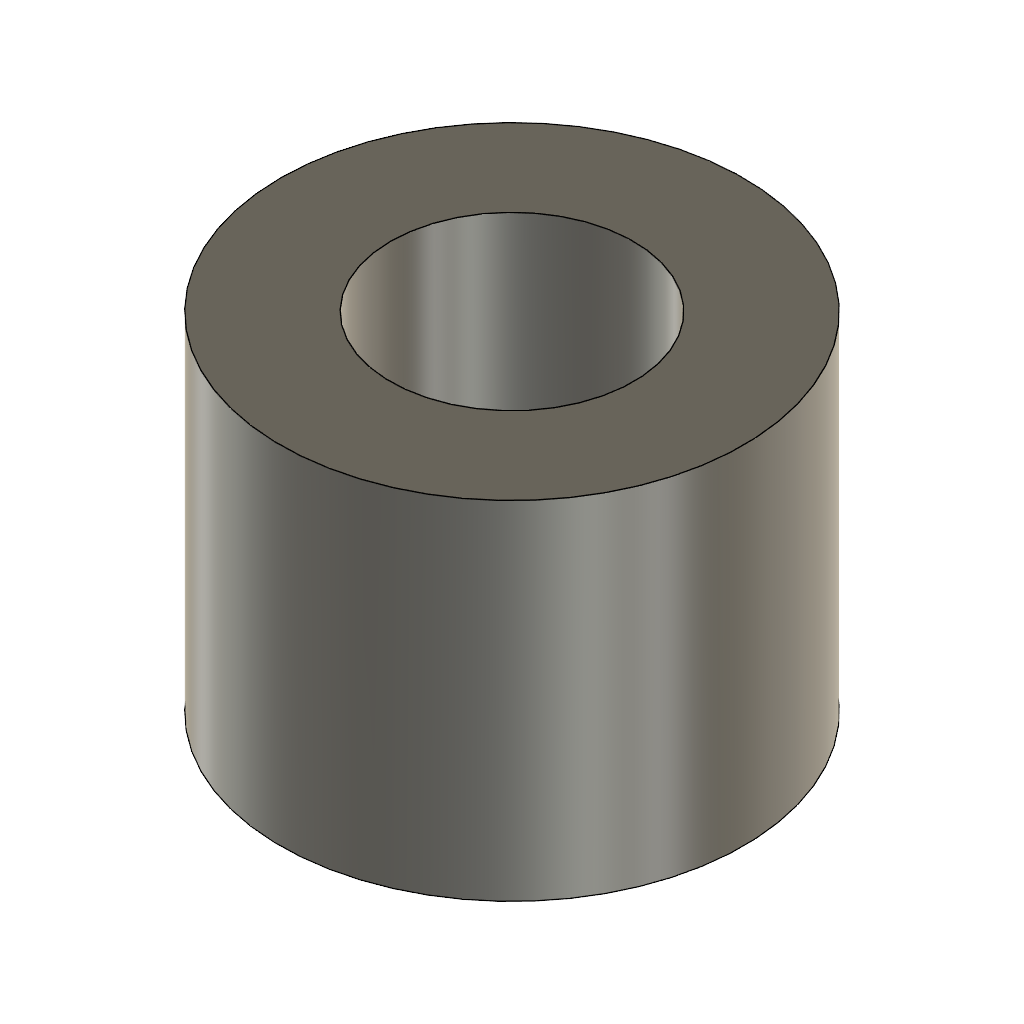
TensionWheel (Autodesk Fusion 360 design; units mm, degrees)
part number: 2026-10-11-19-17-43-800
Autodesk Fusion 360 part; units mm, degrees
sketch "Szkic1" plane through (0, 0, 0) normal (0, 0, 1) x (1, 0, 0)
  circle A0 centre (0, 0) radius 2.1
  circle A1 centre (0, 0) radius 4
  dimension "d1" = 4.2
  dimension "d5" = 8
  constraint coincident A0.centre A1.centre
  measures "d1" diameter of A0
  measures "d5" diameter of A1
extrude "Wyciągnięcie proste1" add sketch "Szkic1" along normal blind 6
